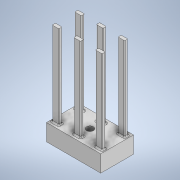
# Autodesk Inventor part: culisant_new_1
Saved by Autodesk Inventor 2022.6 (Build 266554000, 554)
## iProperties
Created: 2026-01-10
Part Number: culisant_new_1
Material: Generic
Document SubType Name: Modeling
Designer: Dragos Macovei
Density: 1 g/cm^3
Appearance: Default
Author: Dragos Macovei
Autodesk Inventor part; units mm, degrees
ref_plane "YZ Plane" through (0, 0, 0) normal (1, 0, 0) x (0, 1, 0)
ref_plane "XZ Plane" through (0, 0, 0) normal (0, 1, 0) x (-1, 0, 0)
ref_plane "XY Plane" through (0, 0, 0) normal (0, 0, 1) x (1, 0, 0)
sketch "Sketch1" plane through (0, 0, 0) normal (0, 1, 0) x (-1, 0, 0)
  line L0 (-77.8595, -28.6159) -> (-77.8595, -23.5601)
  line L1 (-77.8595, -23.5601) -> (-67.6468, -23.5601)
  line L2 (-67.6468, -23.5601) -> (-67.6468, -28.6159)
  line L3 (-67.6468, -28.6159) -> (-77.8595, -28.6159)
  line L4 (-45.5529, -28.6159) -> (-45.5529, -23.5601)
  line L5 (-45.5529, -23.5601) -> (-35.3401, -23.5601)
  line L6 (-35.3401, -23.5601) -> (-35.3401, -28.6159)
  line L7 (-35.3401, -28.6159) -> (-45.5529, -28.6159)
  line L8 (-13.2462, -28.6159) -> (-13.2462, -23.5601)
  line L9 (-13.2462, -23.5601) -> (-3.0335, -23.5601)
  line L10 (-3.0335, -23.5601) -> (-3.0335, -28.6159)
  line L11 (-3.0335, -28.6159) -> (-13.2462, -28.6159)
  line L12 (-3.0335, 10.1116) -> (-3.0335, 5.0558)
  line L13 (-3.0335, 5.0558) -> (-13.2462, 5.0558)
  line L14 (-13.2462, 5.0558) -> (-13.2462, 10.1116)
  line L15 (-13.2462, 10.1116) -> (-3.0335, 10.1116)
  line L16 (-80.893, 15.1674) -> (-80.893, -33.6717)
  line L17 (-80.893, -33.6717) -> (0, -33.6717)
  line L18 (0, -33.6717) -> (0, 15.1674)
  line L19 (0, 15.1674) -> (-80.893, 15.1674)
  line L20 (-77.8595, 10.1116) -> (-67.6468, 10.1116)
  line L21 (-67.6468, 10.1116) -> (-67.6468, 5.0558)
  line L22 (-67.6468, 5.0558) -> (-77.8595, 5.0558)
  line L23 (-77.8595, 5.0558) -> (-77.8595, 10.1116)
  circle A0 centre (-40.4465, -9.2521) radius 5.1064
  line L24 (-45.5529, 10.1116) -> (-35.3401, 10.1116)
  line L25 (-35.3401, 10.1116) -> (-35.3401, 5.0558)
  line L26 (-35.3401, 5.0558) -> (-45.5529, 5.0558)
  line L27 (-45.5529, 5.0558) -> (-45.5529, 10.1116)
  circle A1 centre (-40.4465, -9.2521) radius 10.1064
  point P0 (0, 0)
  point P1 (0, 0)
  dimension "d0" = 5
  constraints: 56 end point, 2 centre point, 1 coincident
  measures "d0" radial gap between concentric circles of A0 A1
extrude "Extrusion1" add sketch "Sketch1" along normal blind 150 contours L0 L1 L2 L3 | L4 L5 L6 L7 | L8 L9 L10 L11 | L12 L13 L14 L15 | L20 L21 L22 L23 | L24 L25 L26 L27
sketch "Sketch2" plane through (0, 0, 0) normal (0, -1, 0) x (1, 0, 0)
  point P0 (0, 0)
sketch "Sketch3" plane through (0, 0, 0) normal (0, 1, 0) x (-1, 0, 0)
  line L0 (-13.2462, -28.6159) -> (-13.2462, -23.5601)
  line L1 (-13.2462, -23.5601) -> (-3.0335, -23.5601)
  line L2 (-3.0335, -28.6159) -> (-13.2462, -28.6159)
  line L3 (-3.0335, -23.5601) -> (-3.0335, -28.6159)
  line L4 (-45.5529, 5.0558) -> (-45.5529, 10.1116)
  line L5 (-67.6468, -23.5601) -> (-67.6468, -28.6159)
  line L6 (-67.6468, 10.1116) -> (-67.6468, 5.0558)
  line L7 (-80.893, 15.1674) -> (-80.893, -33.6717)
  line L8 (-77.8595, 5.0558) -> (-77.8595, 10.1116)
  line L9 (-77.8595, 10.1116) -> (-67.6468, 10.1116)
  line L10 (-67.6468, 5.0558) -> (-77.8595, 5.0558)
  line L11 (-77.8595, -23.5601) -> (-67.6468, -23.5601)
  line L12 (-67.6468, -28.6159) -> (-77.8595, -28.6159)
  line L13 (-45.5529, -28.6159) -> (-45.5529, -23.5601)
  line L14 (-77.8595, -28.6159) -> (-77.8595, -23.5601)
  line L15 (-35.3401, -23.5601) -> (-35.3401, -28.6159)
  line L16 (-3.0335, 5.0558) -> (-13.2462, 5.0558)
  line L17 (-13.2462, 5.0558) -> (-13.2462, 10.1116)
  line L18 (-3.0335, 10.1116) -> (-3.0335, 5.0558)
  line L19 (-13.2462, 10.1116) -> (-3.0335, 10.1116)
  line L20 (-45.5529, -23.5601) -> (-35.3401, -23.5601)
  line L21 (-35.3401, -28.6159) -> (-45.5529, -28.6159)
  line L22 (0, -33.6717) -> (0, 15.1674)
  circle A0 centre (-40.4465, -9.2521) radius 5.1064
  line L23 (-80.893, -33.6717) -> (0, -33.6717)
  line L24 (0, 15.1674) -> (-80.893, 15.1674)
  line L25 (-35.3401, 10.1116) -> (-35.3401, 5.0558)
  line L26 (-35.3401, 5.0558) -> (-45.5529, 5.0558)
  line L27 (-45.5529, 10.1116) -> (-35.3401, 10.1116)
  circle A1 centre (-40.4465, -9.2521) radius 10.1064
  point P0 (0, 0)
  point P1 (0, 0)
  point P2 (0, 0)
  dimension "d3" = 5
  constraints: 56 end point, 2 centre point, 1 coincident
  measures "d3" radial gap between concentric circles of A0 A1
extrude "Extrusion2" add sketch "Sketch3" along normal blind 25 contours A1
sketch "Sketch4" plane through (0, 0, 0) normal (0, 1, 0) x (-1, 0, 0)
  line L0 (-13.2462, -28.6159) -> (-13.2462, -23.5601)
  line L1 (-13.2462, -23.5601) -> (-3.0335, -23.5601)
  line L2 (-3.0335, -28.6159) -> (-13.2462, -28.6159)
  line L3 (-3.0335, -23.5601) -> (-3.0335, -28.6159)
  line L4 (-45.5529, 5.0558) -> (-45.5529, 10.1116)
  line L5 (-67.6468, -23.5601) -> (-67.6468, -28.6159)
  line L6 (-67.6468, 10.1116) -> (-67.6468, 5.0558)
  line L7 (-80.893, 15.1674) -> (-80.893, -33.6717)
  line L8 (-77.8595, 5.0558) -> (-77.8595, 10.1116)
  line L9 (-77.8595, 10.1116) -> (-67.6468, 10.1116)
  line L10 (-67.6468, 5.0558) -> (-77.8595, 5.0558)
  line L11 (-77.8595, -23.5601) -> (-67.6468, -23.5601)
  line L12 (-67.6468, -28.6159) -> (-77.8595, -28.6159)
  line L13 (-45.5529, -28.6159) -> (-45.5529, -23.5601)
  line L14 (-77.8595, -28.6159) -> (-77.8595, -23.5601)
  line L15 (-35.3401, -23.5601) -> (-35.3401, -28.6159)
  line L16 (-3.0335, 5.0558) -> (-13.2462, 5.0558)
  line L17 (-13.2462, 5.0558) -> (-13.2462, 10.1116)
  line L18 (-3.0335, 10.1116) -> (-3.0335, 5.0558)
  line L19 (-13.2462, 10.1116) -> (-3.0335, 10.1116)
  line L20 (-45.5529, -23.5601) -> (-35.3401, -23.5601)
  line L21 (-35.3401, -28.6159) -> (-45.5529, -28.6159)
  line L22 (0, -33.6717) -> (0, 15.1674)
  circle A0 centre (-40.4465, -9.2521) radius 5.1064
  line L23 (-80.893, -33.6717) -> (0, -33.6717)
  line L24 (0, 15.1674) -> (-80.893, 15.1674)
  line L25 (-35.3401, 10.1116) -> (-35.3401, 5.0558)
  line L26 (-35.3401, 5.0558) -> (-45.5529, 5.0558)
  line L27 (-45.5529, 10.1116) -> (-35.3401, 10.1116)
  circle A1 centre (-40.4465, -9.2521) radius 10.1064
  point P0 (0, 0)
  point P1 (0, 0)
  point P2 (0, 0)
  dimension "d6" = 5
  constraints: 56 end point, 2 centre point, 1 coincident
  measures "d6" radial gap between concentric circles of A0 A1
extrude "Extrusion3" add sketch "Sketch4" along normal up to surface (25 mm away) contours L24 L22 L23 L7
sketch "Sketch5" plane through (0, 150, 0) normal (0, 1, 0) x (1, 0, 0)
  line L0 (77.8595, -10.1116) -> (77.8595, -5.0558) projected
  line L1 (77.8595, -5.0558) -> (67.6468, -5.0558) projected
  line L2 (67.6468, -5.0558) -> (67.6468, -10.1116) projected
  line L3 (67.6468, -10.1116) -> (77.8595, -10.1116) projected
  line L4 (35.3401, -5.0558) -> (35.3401, -10.1116) projected
  line L5 (35.3401, -10.1116) -> (45.5529, -10.1116) projected
  line L6 (45.5529, -10.1116) -> (45.5529, -5.0558) projected
  line L7 (45.5529, -5.0558) -> (35.3401, -5.0558) projected
  line L8 (3.0335, -10.1116) -> (13.2462, -10.1116) projected
  line L9 (13.2462, -10.1116) -> (13.2462, -5.0558) projected
  line L10 (13.2462, -5.0558) -> (3.0335, -5.0558) projected
  line L11 (3.0335, -5.0558) -> (3.0335, -10.1116) projected
  line L12 (0, -15.1674) -> (0, 33.6717) projected
  line L13 (80.893, -15.1674) -> (0, -15.1674) projected
  line L14 (80.893, 33.6717) -> (80.893, -15.1674) projected
  line L15 (0, 33.6717) -> (80.893, 33.6717) projected
  line L16 (67.6468, -10.1116) -> (77.8595, -10.1116) projected
  line L17 (67.6468, -5.0558) -> (67.6468, -10.1116) projected
  line L18 (77.8595, -5.0558) -> (67.6468, -5.0558) projected
  line L19 (77.8595, -10.1116) -> (77.8595, -5.0558) projected
  line L20 (13.2462, -5.0558) -> (3.0335, -5.0558) projected
  line L21 (13.2462, -10.1116) -> (13.2462, -5.0558) projected
  line L22 (3.0335, -10.1116) -> (13.2462, -10.1116) projected
  line L23 (3.0335, -5.0558) -> (3.0335, -10.1116) projected
  line L24 (67.6468, 23.5601) -> (77.8595, 23.5601) projected
  line L25 (67.6468, 28.6159) -> (67.6468, 23.5601) projected
  line L26 (77.8595, 28.6159) -> (67.6468, 28.6159) projected
  line L27 (77.8595, 23.5601) -> (77.8595, 28.6159) projected
  line L28 (35.3401, -5.0558) -> (35.3401, -10.1116) projected
  line L29 (45.5529, -5.0558) -> (35.3401, -5.0558) projected
  line L30 (45.5529, -10.1116) -> (45.5529, -5.0558) projected
  line L31 (35.3401, -10.1116) -> (45.5529, -10.1116) projected
  line L32 (35.3401, 23.5601) -> (45.5529, 23.5601) projected
  line L33 (35.3401, 28.6159) -> (35.3401, 23.5601) projected
  line L34 (45.5529, 28.6159) -> (35.3401, 28.6159) projected
  line L35 (45.5529, 23.5601) -> (45.5529, 28.6159) projected
  line L36 (13.2462, 28.6159) -> (3.0335, 28.6159) projected
  line L37 (13.2462, 23.5601) -> (13.2462, 28.6159) projected
  line L38 (3.0335, 23.5601) -> (13.2462, 23.5601) projected
  line L39 (3.0335, 28.6159) -> (3.0335, 23.5601) projected
  circle A0 centre (40.4465, 9.2521) radius 5.1064 projected
  line L40 (77.7095, -9.9616) -> (67.7968, -9.9616)
  line L41 (67.7968, -9.9616) -> (67.7968, -5.2058)
  line L42 (67.7968, -5.2058) -> (77.7095, -5.2058)
  line L43 (77.7095, -5.2058) -> (77.7095, -9.9616)
  line L44 (45.4029, -9.9616) -> (35.4901, -9.9616)
  line L45 (35.4901, -9.9616) -> (35.4901, -5.2058)
  line L46 (35.4901, -5.2058) -> (45.4029, -5.2058)
  line L47 (45.4029, -5.2058) -> (45.4029, -9.9616)
  line L48 (13.0962, -9.9616) -> (3.1835, -9.9616)
  line L49 (3.1835, -9.9616) -> (3.1835, -5.2058)
  line L50 (3.1835, -5.2058) -> (13.0962, -5.2058)
  line L51 (13.0962, -5.2058) -> (13.0962, -9.9616)
  line L52 (13.0962, 23.7101) -> (3.1835, 23.7101)
  line L53 (3.1835, 23.7101) -> (3.1835, 28.4659)
  line L54 (3.1835, 28.4659) -> (13.0962, 28.4659)
  line L55 (13.0962, 28.4659) -> (13.0962, 23.7101)
  line L56 (45.4029, 23.7101) -> (35.4901, 23.7101)
  line L57 (35.4901, 23.7101) -> (35.4901, 28.4659)
  line L58 (35.4901, 28.4659) -> (45.4029, 28.4659)
  line L59 (45.4029, 28.4659) -> (45.4029, 23.7101)
  line L60 (77.7095, 23.7101) -> (67.7968, 23.7101)
  line L61 (67.7968, 23.7101) -> (67.7968, 28.4659)
  line L62 (67.7968, 28.4659) -> (77.7095, 28.4659)
  line L63 (77.7095, 28.4659) -> (77.7095, 23.7101)
  point P0 (0, 0)
  point P1 (8.1399, 23.7101)
  point P2 (40.4465, -10.1116)
  dimension "d9" = 0.15
  dimension "d10" = 0.15
  dimension "d11" = 0.15
  dimension "d12" = 0.15
  dimension "d13" = 0.15
  dimension "d14" = 0.15
  dimension "d15" = 0.15
  dimension "d16" = 0.15
  dimension "d17" = 0.15
  dimension "d18" = 0.15
  dimension "d19" = 0.15
  dimension "d20" = 0.15
  dimension "d21" = 0.15
  dimension "d22" = 0.15
  dimension "d23" = 0.15
  dimension "d24" = 0.15
  dimension "d25" = 0.15
  dimension "d26" = 0.15
  dimension "d27" = 0.15
  constraints: 48 end point, 12 parallel, 6 horizontal, 6 perpendicular, 5 point on line, 2 midpoint
  measures "d9" distance between parallel lines of L27 L63
  measures "d10" distance between parallel lines of L25 L61
  measures "d11" distance between parallel lines of L24 L60
  measures "d12" distance between parallel lines of L26 L62
  measures "d13" distance between parallel lines of L34 L58
  measures "d14" distance between parallel lines of L35 L59
  measures "d15" distance between parallel lines of L33 L57
  measures "d16" distance from line of L38 point (8.14, 23.71)
  measures "d17" distance between parallel lines of L37 L55
  measures "d18" distance between parallel lines of L36 L54
  measures "d19" distance between parallel lines of L39 L53
  measures "d20" distance between parallel lines of L10 L50
  measures "d21" distance between parallel lines of L8 L48
  measures "d22" distance from line of L44 point (40.446, -10.112)
  measures "d23" distance between parallel lines of L4 L45
  measures "d24" distance between parallel lines of L6 L47
  measures "d25" distance between parallel lines of L0 L43
  measures "d26" distance between parallel lines of L2 L41
  measures "d27" distance between parallel lines of L1 L42
extrude "Extrusion4" cut sketch "Sketch5" against normal up to surface (125 mm away) contours L3 L2 L1 L0 | L7 L6 L5 L4 | L11 L10 L9 L8 | L25 L26 L27 L24 | L33 L34 L35 L32 | L37 L38 L39 L36
fillet "Fillet1" radius 1 24 edges at (77.7095, 87.5, 5.2058) (67.7968, 87.5, 5.2058) (77.7095, 87.5, -28.4659) (67.7968, 87.5, -28.4659) (45.4029, 87.5, -28.4659) (35.4901, 87.5, -28.4659) (13.0962, 87.5, -28.4659) (3.1835, 87.5, -28.4659) (3.1835, 87.5, 5.2058) (13.0962, 87.5, 5.2058) (35.4901, 87.5, 5.2058) (45.4029, 87.5, 5.2058) (3.1835, 87.5, 9.9616) (3.1835, 87.5, -23.7101) (35.4901, 87.5, -23.7101) (67.7968, 87.5, -23.7101) (35.4901, 87.5, 9.9616) (67.7968, 87.5, 9.9616) (77.7095, 87.5, -23.7101) (77.7095, 87.5, 9.9616) (45.4029, 87.5, -23.7101) (45.4029, 87.5, 9.9616) (13.0962, 87.5, 9.9616) (13.0962, 87.5, -23.7101)
fillet "Fillet2" radius 2 48 edges at (77.4166, 25, 9.6687) (77.7095, 25, 7.5837) (77.4166, 25, 5.4987) (72.7531, 25, 5.2058) (68.0896, 25, 5.4987) (67.7968, 25, 7.5837) (68.0896, 25, 9.6687) (72.7531, 25, 9.9616) (45.11, 25, 9.6687) (45.4029, 25, 7.5837) (45.11, 25, 5.4987) (40.4465, 25, 5.2058) (35.783, 25, 5.4987) (35.4901, 25, 7.5837) (35.783, 25, 9.6687) (40.4465, 25, 9.9616) (12.8033, 25, 9.6687) (13.0962, 25, 7.5837) (12.8033, 25, 5.4987) (8.1399, 25, 5.2058) (3.4764, 25, 5.4987) (3.1835, 25, 7.5837) (3.4764, 25, 9.6687) (8.1399, 25, 9.9616) (77.4166, 25, -24.003) (77.7095, 25, -26.088) (77.4166, 25, -28.173) (72.7531, 25, -28.4659) (68.0896, 25, -28.173) (67.7968, 25, -26.088) (68.0896, 25, -24.003) (72.7531, 25, -23.7101) (45.11, 25, -24.003) (45.4029, 25, -26.088) (45.11, 25, -28.173) (40.4465, 25, -28.4659) (35.783, 25, -28.173) (35.4901, 25, -26.088) (35.783, 25, -24.003) (40.4465, 25, -23.7101) (12.8033, 25, -24.003) (13.0962, 25, -26.088) (12.8033, 25, -28.173) (8.1399, 25, -28.4659) (3.4764, 25, -28.173) (3.1835, 25, -26.088) (3.4764, 25, -24.003) (8.1399, 25, -23.7101)
body "Solid1"
